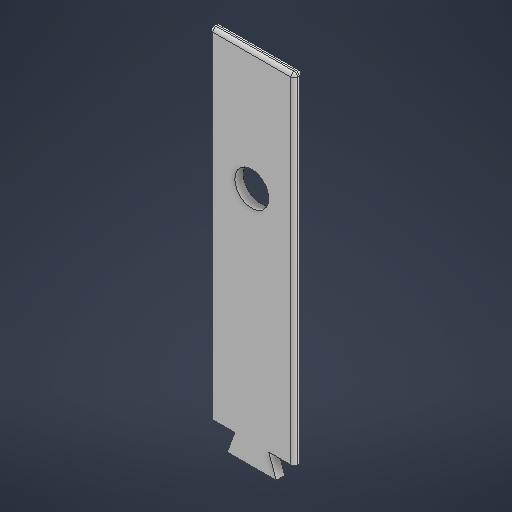
# Autodesk Inventor part: pantorillaup2
Saved by Autodesk Inventor 2027.1 (Build 311270010, 270A)
## iProperties
Created: 2026-11-19
Part Number: pantorillaup2
Material: Generic
Document SubType Name: Modeling
Designer: ASUS
Density: 1 g/cm^3
Appearance: Default
Author: ASUS
Autodesk Inventor part; units mm, degrees
ref_plane "YZ Plane" through (0, 0, 0) normal (1, 0, 0) x (0, 1, 0)
ref_plane "XZ Plane" through (0, 0, 0) normal (0, 1, 0) x (-1, 0, 0)
ref_plane "XY Plane" through (0, 0, 0) normal (0, 0, 1) x (1, 0, 0)
sketch "Sketch1" plane through (0, 0, 0) normal (0, 0, 1) x (1, 0, 0)
  line L0 (-10, -38.0442) -> (40, -38.0442)
  line L1 (40, -38.0442) -> (40, 321.9558)
  line L2 (40, 321.9558) -> (-10, 321.9558)
  line L3 (-10, 321.9558) -> (-10, -38.0442)
  line L4 (-10, 121.9558) -> (5, 121.9558)
  line L5 (5, 121.9558) -> (0.5537, 109.7398)
  line L6 (40, 121.9558) -> (25, 121.9558)
  line L7 (25, 121.9558) -> (29.4463, 109.7398)
  line L8 (29.4463, 109.7398) -> (0.5537, 109.7398)
  circle A0 centre (15, -13.0442) radius 10
  point P0 (-2.5, 121.9558)
  dimension "d0" = 50
  dimension "d1" = 360
  dimension "d24" = 15
  dimension "d25" = 13
  dimension "d26" = 70
  dimension "d27" = 15
  dimension "d28" = 13
  dimension "d29" = 70
  dimension "d30" = 200
  dimension "d31" = 20
  dimension "d32" = 25
  dimension "d33" = 25
  constraints: 18 end point, 3 parallel, 2 horizontal, 2 perpendicular, 2 point on line, 1 centre point, 1 midpoint
  measures "d0" distance of L2.end L1.end
  measures "d1" distance of L1.end L0.end
  measures "d24" distance of L4.start L4.end
  measures "d25" distance of L4.end L5.end
  measures "d26" angle of L4 L5
  measures "d27" distance of L6.start L6.end
  measures "d28" distance of L6.end L7.end
  measures "d29" angle of L7 L6
  measures "d30" distance from line of point (-2.5, 121.956) L2
  measures "d31" diameter of A0
  measures "d32" distance from line of L1 A0.centre
  measures "d33" distance from line of L0 A0.centre
extrude "Extrusion1" add sketch "Sketch1" along normal blind 5 contours L3 L2 L1 L6 L7 L8 L5 L4
sketch "Sketch3" plane through (-10, 321.9558, 5) normal (0, 0, 1) x (1, 0, 0)
  circle A0 centre (25, -70.5) radius 10
  line L0 (0, 0) -> (0, -150.1667) projected
  line L1 (50, 0) -> (0, 0) projected
  point P0 (10, -321.9558)
  point P1 (25, 0)
  dimension "d11" = 20
  dimension "d22" = 25
  dimension "d23" = 70.5
  constraints: 1 centre point, 1 midpoint
  measures "d11" diameter of A0
  measures "d22" distance from line of A0.centre L0
  measures "d23" distance of A0.centre point (25, 0)
extrude "Extrusion2" cut sketch "Sketch3" against normal blind 5
fillet "Fillet1" radius 2 1 edges at (40, 321.9558, 2.5)
fillet "Fillet2" radius 2 1 edges at (-10, 321.9558, 2.5)
fillet "Fillet3" radius 2 5 edges at (15, 321.9558, 5) (-9.4142, 321.37, 5) (-10, 220.9558, 5) (39.4142, 321.37, 5) (40, 220.9558, 5)
fillet "Fillet5" radius 2 5 edges at (40, 220.9558, 0) (39.4142, 321.37, 0) (15, 321.9558, 0) (-9.4142, 321.37, 0) (-10, 220.9558, 0)
body "Solid1"
